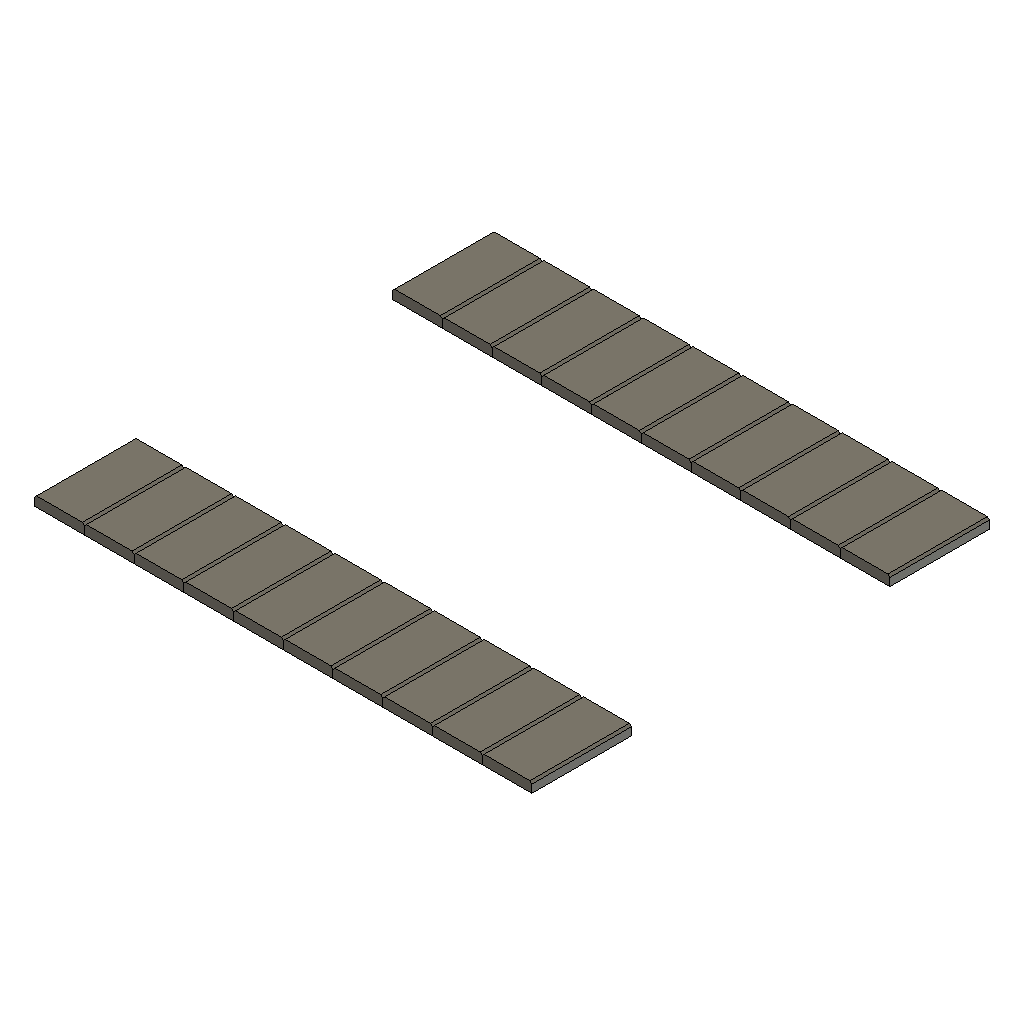
Coaster (Autodesk Fusion 360 archive; units mm, degrees)
design "plank2"
part number: 2026-10-19-14-20-50-345
Autodesk Fusion 360 part; units mm, degrees
sketch "Sketch1" plane through (0, 0, 0) normal (0, 1, 0) x (1, 0, 0)
  line L0 (0, 0) -> (2.5, 0)
  line L1 (2.5, 0) -> (2.5, -5)
  line L2 (2.5, -5) -> (0, -5)
  line L3 (0, -5) -> (0, 0)
  dimension "d1" = 2.5
  dimension "d2" = 5
  constraint horizontal L0
  constraint vertical L1
  constraint horizontal L2
  constraint vertical L3
  constraint coincident L0.start L3.end
  measures "d1" distance of L0.start L0.end
  measures "d2" distance of L0.start L2.end
extrude "Extrude1" add sketch "Sketch1" along normal blind 0.5 makes body 1
chamfer "Chamfer1" distance 0.1 angle 45 1 faces at (0.8333, 0.5, 1.6667) tangent chain off on bodies 1
delete_face "DeleteFace1" 1 faces at (0.8667, 0.4333, 4.9667) on bodies 1
delete_face "DeleteFace2" 1 faces at (1.6333, 0.4333, 0.0333) on bodies 1
pattern_linear "R-Pattern1" count 10 spacing 2.5 along (1, 0, 0) of bodies 1 makes body 2 at (3.3333, 0, 1.6667) makes body 3 at (5.8333, 0, 1.6667) makes body 4 at (8.3333, 0, 1.6667) makes body 5 at (10.8333, 0, 1.6667) makes body 6 at (13.3333, 0, 1.6667) makes body 7 at (15.8333, 0, 1.6667) makes body 8 at (18.3333, 0, 1.6667) makes body 9 at (20.8333, 0, 1.6667) makes body 10 at (23.3333, 0, 1.6667)
copy_body "CopyPasteBodies1" bodies 1 9 3 8 6 7 5 4 2 10 makes body 11 makes body 12 makes body 13 makes body 14 makes body 15 makes body 16 makes body 17 makes body 18 makes body 19 makes body 20
move_body "Move1" bodies 11 12 13 14 15 16 17 18 19 20 to x (1, 0, 0) y (0, 1, 0) z (0, 0, 1) at (0, 0, -18)

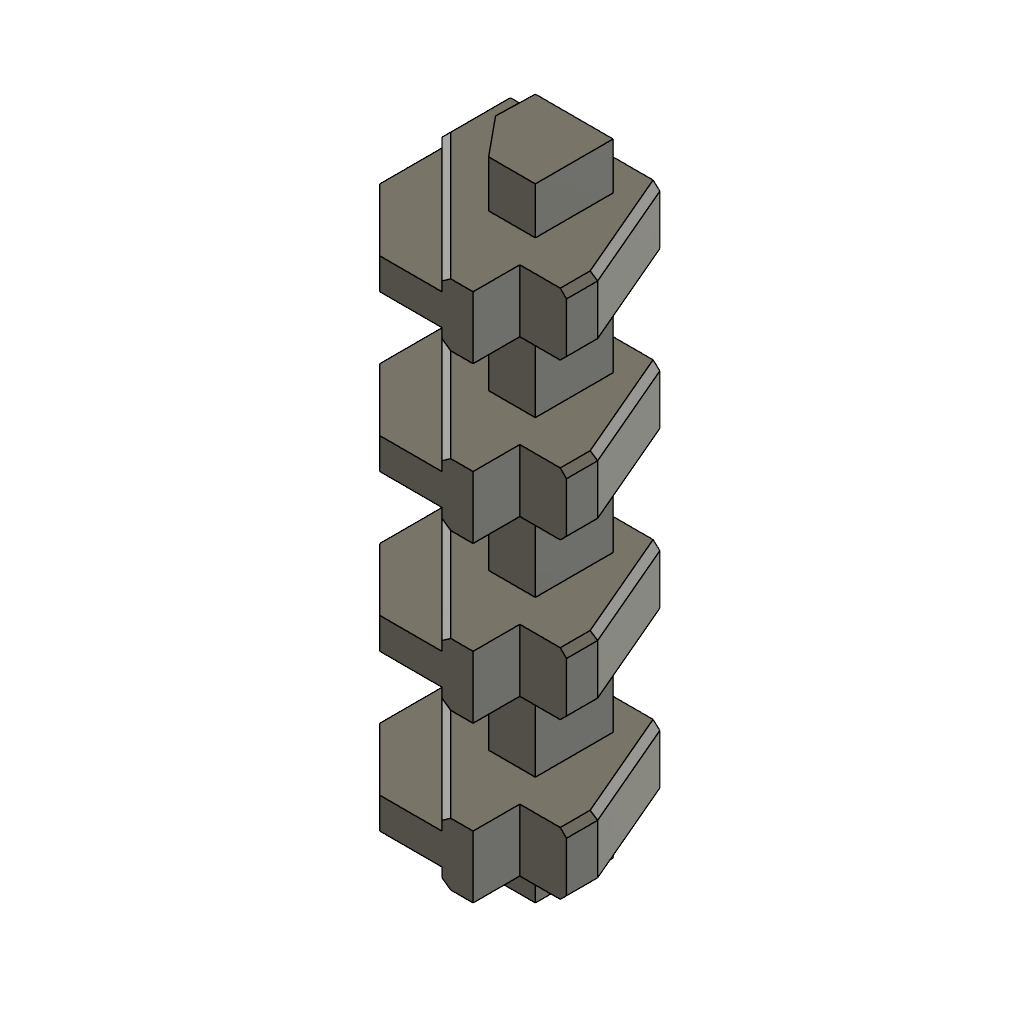
design "Station SideRails"
part number: 2026-10-16-17-27-23-108
Autodesk Fusion 360 part; units mm, degrees
sketch "Sketch1" plane through (0, 0, 0) normal (0, 1, 0) x (1, 0, 0)
  line L0 (2, 0) -> (5, 0)
  line L1 (2, 0) -> (0, 2)
  line L2 (5, 2.5) -> (5, 0)
  line L3 (0, 6) -> (5, 6)
  line L4 (0, 6) -> (0, 2)
  line L5 (5, 6) -> (5, 0)
  point P0 (1, 1.0104)
  dimension "d1" = 5
  dimension "d3" = 2
  dimension "d141" = 6
  constraint horizontal L0
  constraint coincident origin L0
  constraint vertical L2
  measures "d1" distance of origin L0.end
  measures "d3" distance of origin L0.start
  measures "d141" distance of L0.end L3.end
sketch "Sketch2" plane through (0, 0, 0) normal (0, 1, 0) x (1, 0, 0)
  line L0 (1, 9) -> (4, 9)
  line L1 (4, 9) -> (4, 6)
  line L2 (4, 6) -> (1, 6)
  line L3 (1, 6) -> (1, 9)
  dimension "d15" = 3
  dimension "d16" = 3
  constraint horizontal L0
  constraint vertical L1
  constraint horizontal L2
  constraint vertical L3
  measures "d15" distance of L0.start L0.end
  measures "d16" distance of L0.start L2.end
pattern_linear "R-Pattern1" [no effect]
move_body "Move2" [no effect]
move_body "Move3" [no effect]
move_body "Move4" [no effect]
move_body "Move7" [no effect]
sketch "Sketch7" plane through (0, 0, 0) normal (0, 1, 0) x (1, 0, 0)
  line L0 (0, 6) -> (1.5, 6)
  line L1 (5, 0) -> (4, 0)
  line L2 (0, 4) -> (0, 6)
  line L3 (4, 0) -> (0, 4)
  line L4 (1.5, 6) -> (5, 6)
  line L5 (1.5, 6) -> (5, 6)
  line L6 (5, 1.5) -> (6.5, 1.5)
  line L7 (6.5, 1.5) -> (6.5, 2.5)
  line L8 (6.5, 2.5) -> (5, 6)
  line L9 (5, 0) -> (5, 1.5)
  line L10 (2.9997, 2.5) -> (4.4997, 2.5)
  line L11 (4.4997, 2.5) -> (4.4997, 5)
  line L12 (1.9997, 5) -> (1.9719, 3.75)
  line L13 (1.9719, 3.75) -> (2.9997, 2.5)
  line L14 (1.9997, 5) -> (4.4997, 5)
  point P0 (5, 6)
  point P1 (1, 2.5)
  dimension "d142" = 4
  dimension "d143" = 4
  dimension "d144" = 2
  dimension "d145" = 1
  dimension "d146" = 1.5
  dimension "d147" = 1
  dimension "d148" = 5
  dimension "d149" = 2.5
  dimension "d150" = 2.5
  dimension "d151" = 1.5
  dimension "d152" = 1.25
  constraint horizontal L0
  constraint horizontal L1
  constraint vertical L2
  constraint coincident origin L1
  constraint coincident origin L2
  constraint coincident P0 L0
  constraint coincident P0 L4.end
  constraint perpendicular L6 L7
  constraint perpendicular L6 L9
  constraint horizontal L10
  constraint vertical L11
  constraint coincident P1 L10
  measures "d142" distance of origin L1.end
  measures "d143" distance of origin L2.start
  measures "d144" distance of L0.start L2.start
  measures "d145" distance of L1.start L1.end
  measures "d146" distance of L6.start L6.end
  measures "d147" distance of L6.end L7.end
  measures "d148" distance of L0.start P0
  measures "d149" distance of L11.end L12.start
  measures "d150" distance of L11.end L10.end
  measures "d151" distance of L10.end L10.start
  measures "d152" vertical distance of L12.start L12.end
extrude "Extrude19" add sketch "Sketch7" sketch "Sketch1" along normal blind 0.5 and the other way blind 0.5 contours L0 L1 L2 L3 L4 L5 L6 L7 L8 L9 | L10 L11 L12 L13 L14 of sketch 2 makes body 1
extrude "Extrude20" add sketch "Sketch7" along normal blind 1 and the other way blind 1 separate body contours L0 L1 L2 L3 L4 L5 L6 L7 L8 L9 | L10 L11 L12 L13 L14 makes body 2
chamfer "Chamfer13" distance 0.2 angle 45 8 edges at (0, 1, -5) (2, 1, -2) (0, -1, -5) (2, -1, -2) (5.75, -1, -4.25) (6.5, -1, -2) (5.75, 1, -4.25) (6.5, 1, -2) tangent chain off on bodies 2
extrude "Extrude21" add sketch "Sketch7" along normal blind 19 and the other way blind 1 separate body contours L10 L11 L12 L13 L14 makes body 3
copy_body "CopyPasteBodies13" bodies 2 makes body 4
move_body "Move28" bodies 4 to x (1, 0, 0) y (0, 1, 0) z (0, 0, 1) at (0, 5, 0)
copy_body "CopyPasteBodies14" bodies 4 makes body 5
move_body "Move29" bodies 5 to x (1, 0, 0) y (0, 1, 0) z (0, 0, 1) at (0, 5, 0)
copy_body "CopyPasteBodies15" bodies 5 makes body 6
move_body "Move30" bodies 6 to x (1, 0, 0) y (0, 1, 0) z (0, 0, 1) at (0, 5, 0)
copy_body "CopyPasteBodies16" bodies 1 makes body 7
move_body "Move31" bodies 7 to x (1, 0, 0) y (0, 1, 0) z (0, 0, 1) at (0, 5, 0)
copy_body "CopyPasteBodies17" bodies 7 makes body 8
move_body "Move32" bodies 8 to x (1, 0, 0) y (0, 1, 0) z (0, 0, 1) at (0, 5, 0)
copy_body "CopyPasteBodies18" bodies 8 makes body 9
move_body "Move33" bodies 9 to x (1, 0, 0) y (0, 1, 0) z (0, 0, 1) at (0, 5, 0)
move_body "Move34" bodies 9 8 7 5 6 1 2 4 to x (1, 0, 0) y (0, 1, 0) z (0, 0, 1) at (0, 1.5, 0)
combine "Combine1" operation add target body 8 tool bodies 4 5 6 1 3 9 2 7
extrude "Extrude9" [rolled back] along distance 2 taper angle 0
extrude "Extrude10" [rolled back] along distance -1 taper angle 0
chamfer "Chamfer5" [rolled back] distance 1
chamfer "Chamfer6" [rolled back] distance 0.5
extrude "Extrude11" [rolled back] along distance -2.5 taper angle 0
sketch "Sketch8" plane through (0, 0, 0) normal (0, 1, 0) x (-1, 0, 0)
extrude "Extrude12" [rolled back] along distance -1 taper angle 0
chamfer "Chamfer7" [rolled back] distance 0.5
chamfer "Chamfer8" [rolled back] distance 0.5
extrude "Extrude5" [rolled back] along distance 1 taper angle 0
move_body "Move11" [rolled back] translate x 0 translate y 1 translate z 0
chamfer "Chamfer1" [rolled back] distance 1
chamfer "Chamfer2" [rolled back] distance 1
sketch "Sketch6" plane through (0, 37, 0) normal (0, 1, 0) x (-1, 0, 0)
  line L0 (0, -6.1667) -> (0, -5.1667)
  line L1 (0, -5.1667) -> (-5, -1.8333)
  line L2 (-5, -1.8333) -> (-5, -2.8333)
  line L3 (-5, -2.8333) -> (0, -6.1667)
extrude "Extrude8" [rolled back] along distance 1 taper angle 0 against distance 1 side2taper angle 0
